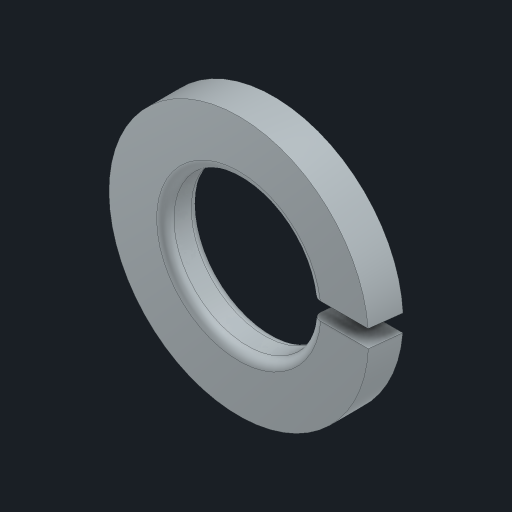
# Autodesk Inventor part: Arruela de Pressão DIN 127 - B3
Saved by Autodesk Inventor 2024.3 (Build 283343000, 343)
## iProperties
Created: 2025-07-13
Part Number: Arruela de Pressão DIN 127 - B3
Material: Aço, carbono
Document SubType Name: Modeling
Designer: Cliente
Mass: 0.115852 g
Surface Area: 0.606643 cm^2
Volume: 0.0147582 cm^3
Density: 7.85 g/cm^3
Appearance: Zinco
Author: Cliente
Autodesk Inventor part; units mm, degrees
ref_plane "XZ Plane" through (0, 0, 0) normal (0, 1, 0) x (-1, 0, 0)
ref_plane "XY Plane" through (0, 0, 0) normal (0, 0, 1) x (1, 0, 0)
sketch "Esboço1" plane through (0, 0, 0) normal (0, 0, 1) x (1, 0, 0)
  circle A0 centre (0, 0) radius 1.7
  circle A1 centre (0, 0) radius 3
  dimension "d0" = 3.4
  dimension "d1" = 6
  constraints: 2 centre point, 2 coincident
  measures "d0" diameter of A0
  measures "d1" diameter of A1
extrude "Extrusão1" add sketch "Esboço1" along normal mid plane 0.8
fillet "Arredondamento1" radius 0.2 2 edges at (-1.7, 0, 0.4) (-1.7, 0, -0.4)
ref_plane "Plano de trabalho1" through (3, 0, 0) normal (1, 0, 0) x (0, 1, 0)
sketch "Esboço2" plane through (3, 0, 0) normal (1, 0, 0) x (0, 1, 0)
  line L0 (0.2, 0) -> (-0.2, 0)
  line L1 (3, 0.4) -> (-3, 0.4) projected
  line L2 (0.242, 0.4) -> (0.158, -0.4)
  line L3 (0.242, 0.4) -> (1.0464, 0.4) construction
  line L4 (-3, -0.4) -> (3, -0.4) projected
  line L5 (-0.158, 0.4) -> (-0.242, -0.4)
  point P0 (0, 0)
  point P1 (0, 0)
  dimension "d5" = 0.4
  dimension "d6" = 96
  constraints: 8 end point, 4 point on line, 3 midpoint, 2 horizontal, 1 coincident, 1 equal length, 1 parallel
  measures "d5" distance of L0.start L0.end
  measures "d6" angle of L2 L3
extrude "Extrusão2" cut sketch "Esboço2" against normal blind 2
